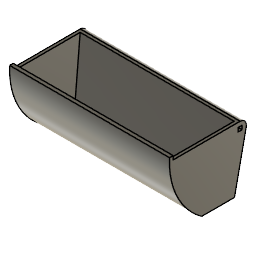
Dumper (Autodesk Fusion 360 design; units mm, degrees)
Autodesk Fusion 360 part; units mm, degrees
sketch "Sketch1" plane through (0, 0, 0) normal (1, 0, 0) x (0, 1, 0)
  line L0 (63.5, 12.7) -> (63.5, 63.5)
  line L1 (63.5, 63.5) -> (0, 63.5)
  line L2 (25.4, 12.7) -> (63.5, 12.7)
  arc A0 (0, 63.5) -> (25.4, 12.7) centre (63.5, 63.5) ccw
  line L3 (66.675, 9.525) -> (66.675, 66.675)
  line L4 (66.675, 66.675) -> (-3.0994, 66.675)
  arc A1 (-3.0994, 66.675) -> (24.356, 9.525) centre (63.5, 63.5) ccw
  line L5 (24.356, 9.525) -> (66.675, 9.525)
  line L6 (0, 63.5) -> (0, 66.675)
  line L7 (66.675, 53.975) -> (66.675, 66.675)
  line L8 (57.4278, 66.675) -> (57.15, 63.5)
  line L9 (57.15, 63.5) -> (52.7056, 12.7)
  line L10 (66.675, 53.975) -> (63.5, 50.8)
  line L11 (54.6003, 63.5) -> (50.1559, 12.7)
  line L12 (63.5, 50.8) -> (55.3235, 42.6235)
  line L13 (52.7056, 12.7) -> (52.4278, 9.525)
  line L14 (50.1559, 12.7) -> (49.8781, 9.525)
  dimension "d2" = 63.5
  dimension "d5" = 3.175
  dimension "d6" = 57.15
  dimension "d7" = 69.7744
  dimension "d8" = 66.675
  dimension "d22" = 6.35
  dimension "d23" = 85
  dimension "d26" = 45
  dimension "d27" = 2.54
  constraint vertical L0
  constraint horizontal L1
  constraint coincident L0.end L1.start
  constraint perpendicular L0 L2
  constraint coincident L4 L6.end
  constraint tangent A0 L6
  constraint vertical L7
  constraint coincident L4 L8.start
  constraint coincident L1 L8.end
  constraint coincident L2 L9.end
  constraint parallel L8 L9
  constraint coincident L0 L10.end
  constraint coincident L1 L11.start
  constraint coincident L2 L11.end
  constraint parallel L9 L11
  constraint coincident L9 L12.end
  constraint parallel L10 L12
  constraint coincident L5 L13.end
  constraint parallel L9 L13
  constraint coincident L5 L14.end
  constraint parallel L11 L14
  measures "d2" distance of origin L1.end
  measures "d6" distance of L3.start L3.end
  measures "d7" distance of L3.end L4.end
  measures "d8" horizontal distance of origin L3.start
  measures "d22" distance of L0.end L8.end
  measures "d23" angle of L2 L9
  measures "d26" angle of L3 L10
  measures "d27" distance of L9 L11
extrude "Extrude1" add sketch "Sketch1" along normal blind 136.525 contours L2 L5 L13 L14 | L1 L2 L9 L11 | L2 A0 L4 A1 L5 L6 L14 | L1 L2 A0 L11
extrude "Extrude2" cut sketch "Sketch1" along normal blind 133.9977 and the other way blind -2.54 contours L0 L2 L9 L12 | L1 L2 A0 L11
sketch "Sketch6" plane through (136.525, 0, 0) normal (1, 0, 0) x (0, 1, 0)
  line L0 (52.4278, 9.525) -> (57.15, 63.5)
  line L1 (57.15, 63.5) -> (0, 63.5)
  line L2 (0, 63.5) -> (0, 66.675)
  line L3 (0, 66.675) -> (-3.0994, 66.675)
  arc A0 (-3.0994, 66.675) -> (24.356, 9.525) centre (63.5, 63.5) ccw
  line L4 (24.356, 9.525) -> (52.4278, 9.525)
  line L5 (57.15, 63.5) -> (57.15, 58.039)
  circle A1 centre (57.15, 58.039) radius 5.461
  line L6 (52.4278, 9.525) -> (62.4918, 56.9043)
  dimension "d38" = 5.461
  constraint coincident L0.end L1.start
  constraint perpendicular L1 L5
  constraint coincident L5.end A1.centre
  constraint coincident L0.end A1
  constraint coincident L0.start L4.end
  constraint coincident A1 L6.end
  constraint tangent A1 L6
  measures "d38" distance of L0.end L5.end
extrude "Extrude7" add sketch "Sketch6" against normal up to surface (136.525 mm away) contours L0 A1 L6 | L0 A1 picked at (59.0752, 59.6844)
sketch "Sketch7" plane through (136.525, 0, 0) normal (1, 0, 0) x (0, 1, 0)
  line L0 (57.15, 63.5) -> (0, 63.5)
  line L1 (0, 63.5) -> (0, 66.675)
  line L2 (0, 66.675) -> (-3.0994, 66.675)
  arc A0 (-3.0994, 66.675) -> (24.356, 9.525) centre (63.5, 63.5) ccw
  line L3 (24.356, 9.525) -> (52.4278, 9.525)
  line L4 (52.4278, 9.525) -> (62.4918, 56.9043)
  arc A1 (62.4918, 56.9043) -> (57.15, 63.5) centre (57.15, 58.039) ccw
  line L5 (58.801, 59.69) -> (55.499, 59.69)
  line L6 (55.499, 59.69) -> (55.499, 56.388)
  line L7 (55.499, 56.388) -> (58.801, 56.388)
  line L8 (58.801, 56.388) -> (58.801, 59.69)
  line L9 (58.801, 59.69) -> (55.499, 56.388) construction
  line L10 (55.499, 59.69) -> (58.801, 56.388) construction
  point P0 (57.15, 58.039)
  dimension "d41" = 3.302
  dimension "d42" = 3.302
  constraint horizontal L5
  constraint perpendicular L5 L6
  constraint parallel L5 L7
  constraint parallel L6 L8
  constraint coincident L9 P0
  constraint coincident L10 P0
  constraint coincident P0 A1.centre
  measures "d41" distance of L6.end L7.end
  measures "d42" distance of L5.end L6.end
extrude "Extrude8" cut sketch "Sketch7" against normal blind 180.34 contours L5 L6 L7 L8
